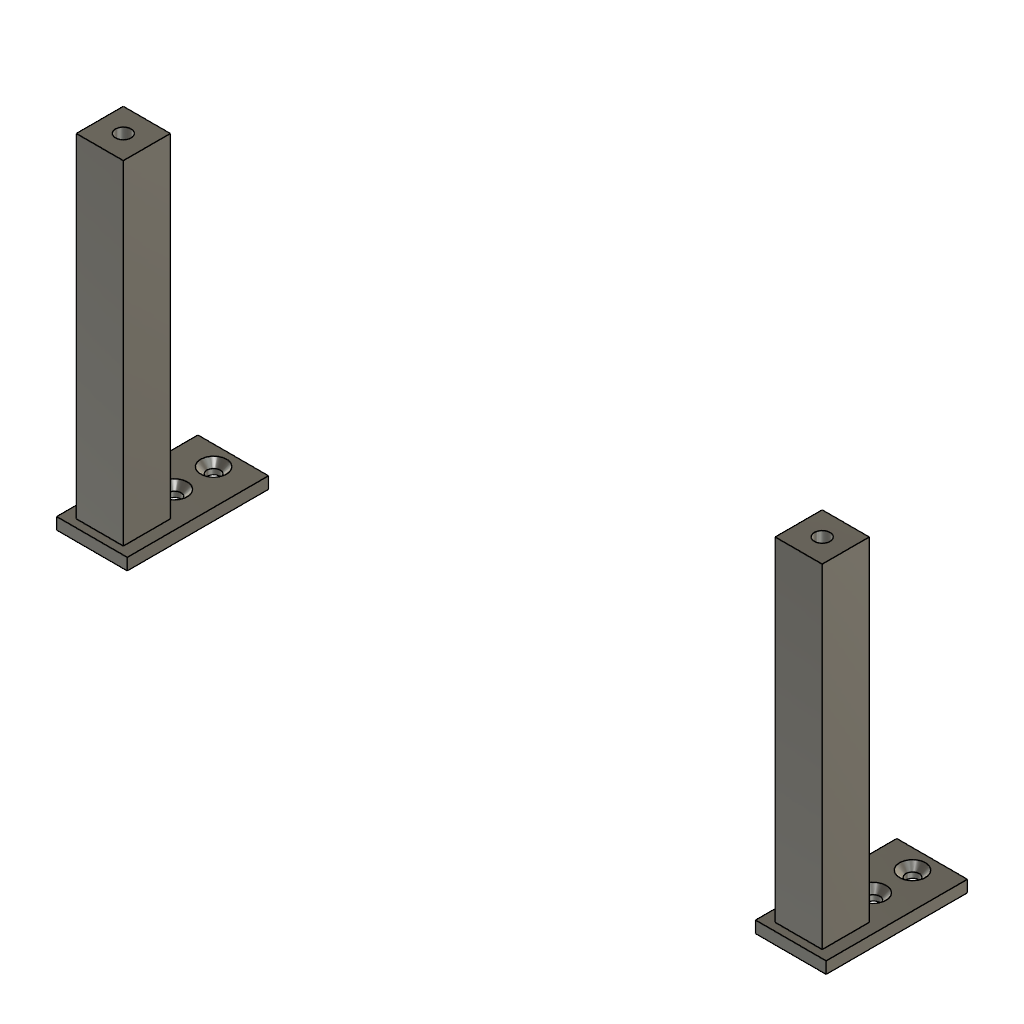
DSLR_Legs (Autodesk Fusion 360 design; units mm, degrees)
part number: 2026-10-19-10-28-44-029
Autodesk Fusion 360 part; units mm, degrees
sketch "leg" plane through (0, 0, 0) normal (0, 0, 1) x (1, 0, 0)
  line L0 (83, 152) -> (95, 152)
  line L1 (95, 152) -> (95, 164)
  line L2 (95, 164) -> (83, 164)
  line L3 (83, 164) -> (83, 152)
extrude "leg (1)" add sketch "leg" along normal blind 88 from surface at 83 makes body 1
sketch "foot" plane through (0, 0, 0) normal (0, 0, 1) x (1, 0, 0)
  line L0 (80, 150) -> (98, 150)
  line L1 (98, 150) -> (98, 186)
  line L2 (98, 186) -> (80, 186)
  line L3 (80, 186) -> (80, 150)
extrude "foot (1)" add sketch "foot" along normal blind 3 from surface at 83 bodies 1
sketch "leg (1)" plane through (0, 0, 0) normal (0, 0, 1) x (1, 0, 0)
  line L0 (-95, 152) -> (-83, 152)
  line L1 (-83, 152) -> (-83, 164)
  line L2 (-83, 164) -> (-95, 164)
  line L3 (-95, 164) -> (-95, 152)
extrude "leg (2)" add sketch "leg (1)" along normal blind 88 from surface at 83 separate body makes body 2
sketch "foot (1)" plane through (0, 0, 0) normal (0, 0, 1) x (1, 0, 0)
  line L0 (-98, 150) -> (-80, 150)
  line L1 (-80, 150) -> (-80, 186)
  line L2 (-80, 186) -> (-98, 186)
  line L3 (-98, 186) -> (-98, 150)
extrude "foot (2)" add sketch "foot (1)" along normal blind 3 from surface at 83 bodies 2
sketch "foot_screws_hole" plane through (0, 0, 0) normal (0, 0, 1) x (1, 0, 0)
  circle A0 centre (89, 171) radius 1.7
  circle A1 centre (89, 181) radius 1.7
  circle A2 centre (-89, 171) radius 1.7
  circle A3 centre (-89, 181) radius 1.7
extrude "foot_screws_hole (1)" cut sketch "foot_screws_hole" against normal blind 4 from surface at 86.5 bodies 1 2
sketch "foot_screws_cone" plane through (0, 0, 0) normal (0, 0, 1) x (1, 0, 0)
  circle A0 centre (89, 171) radius 3.8
  circle A1 centre (89, 181) radius 3.8
  circle A2 centre (-89, 171) radius 3.8
  circle A3 centre (-89, 181) radius 3.8
extrude "foot_screws_cone (1)" cut sketch "foot_screws_cone" against normal blind 2.1 draft -45 from surface at 86.5 bodies 1 2
sketch "leg_top_insert" plane through (0, 0, 0) normal (0, 0, 1) x (1, 0, 0)
  circle A0 centre (89, 158) radius 2
  circle A1 centre (-89, 158) radius 2
extrude "leg_top_insert (1)" cut sketch "leg_top_insert" against normal blind 8.2 from surface at 171.2 bodies 1 2
equation "d1105 = -( 4.00 mm )"
equation "d1108 = -( 2.10 mm )"
equation "d1111 = -( 8.20 mm )"
named bodies: "DSLR Leg R", "DSLR Leg L"
